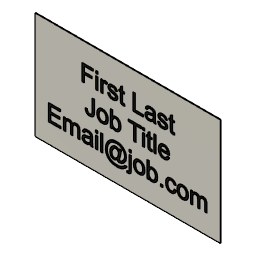
Braille Embosser Assembly v1.0 (Autodesk Fusion 360 archive; units mm, degrees)
design "Business Card v1.0 (Non-Working Example)"
Autodesk Fusion 360 part; units mm, degrees
note: some values were not read from the file. Set by a fixed rule: which face or edge a step refers to.
sketch "Sketch1" plane through (0, 0, 0) normal (0, 1, 0) x (1, 0, 0)
  line L0 (0, 0) -> (90, 0)
  line L1 (90, 0) -> (90, -52)
  line L2 (90, -52) -> (0, -52)
  line L3 (0, -52) -> (0, 0)
  dimension "d1" = 90
  dimension "d2" = 52
  constraint horizontal L0
  constraint vertical L1
  constraint horizontal L2
  constraint vertical L3
  constraint coincident L0.start L3.end
  measures "d1" distance of L0.start L0.end
  measures "d2" distance of L0.start L2.end
extrude "Extrude1" add sketch "Sketch1" along normal blind 0.3 makes body 1
sketch "Sketch2" plane through (0, 0, 0) normal (0, -1, 0) x (1, 0, 0)
  line L0 (90, 52) -> (0, 52)
  line L1 (0, 52) -> (0, 0)
  line L2 (0, 0) -> (90, 0)
  line L3 (90, 0) -> (90, 52)
  line L4 (0, 0) -> (90, 0) construction
  line L5 (90, 0) -> (90, 52) construction
  line L6 (90, 52) -> (0, 52) construction
  line L7 (0, 52) -> (0, 0) construction
  dimension "d5" = 8
  text T0 "First Last\nJob Title\nEmail@job.com" font "Arial" height 8 align centre middle in box 90 x 52 at (0, 0) x (1, 0) y (0, 1) spacing 1 kerned
  constraint coincident L2.end
  constraint coincident L0.end
extrude "Extrude2" cut sketch "Sketch2" against normal blind 0.15 text T0 bodies 1
extrude "Extrude3" add 34 faces at (23.211, 0.15, 38.3638) (30.1651, 0.15, 36.4175) (30.1651, 0.15, 41.7326) (32.3042, 0.15, 37.4288) (38.3852, 0.15, 37.4715) (42.1287, 0.15, 37.276) (47.9422, 0.15, 37.467) (58.0793, 0.15, 36.1309) (62.6143, 0.15, 37.4715) (66.3579, 0.15, 37.276) (28.1223, 0.15, 26.3456) (30.4331, 0.15, 25.2981) (36.9467, 0.15, 25.7442) (48.6335, 0.15, 24.352) (52.839, 0.15, 23.9318) (52.839, 0.15, 29.2469) (55.493, 0.15, 24.7904) (58.3997, 0.15, 24.6667) (63.4748, 0.15, 24.9159) (75.884, 0.15, 12.4484) (69.3417, 0.15, 12.8125) (64.2309, 0.15, 10.6585) (54.7311, 0.15, 13.2585) (48.2176, 0.15, 12.8125) (46.3834, 0.15, 11.2424) (46.3834, 0.15, 16.754) (41.3302, 0.15, 13.769) (32.5389, 0.15, 12.181) (30.0832, 0.15, 16.7613) (30.0832, 0.15, 11.4461) (27.5636, 0.15, 11.1595) (14.2251, 0.15, 12.4484) (6.9436, 0.15, 13.4034) (61.6721, 0.15, 9.8872) along direction (0, -1, 0) blind 0.15 separate body on bodies 1 makes body 2 at (6.9436, 0.15, 13.4034) makes body 3 at (27.5636, 0.15, 11.1595) makes body 4 at (30.0832, 0.15, 16.7613) makes body 5 at (41.3302, 0.15, 13.769) makes body 6 at (46.3834, 0.15, 11.2424) makes body 7 at (54.7311, 0.15, 13.2585) makes body 8 at (69.3417, 0.15, 12.8125) makes body 9 at (63.4748, 0.15, 24.9159) makes body 10 at (55.493, 0.15, 24.7904) makes body 11 at (52.839, 0.15, 23.9318) makes body 12 at (36.9467, 0.15, 25.7442) makes body 13 at (28.1223, 0.15, 26.3456) makes body 14 at (62.6143, 0.15, 37.4715) makes body 15 at (47.9422, 0.15, 37.467) makes body 16 at (38.3852, 0.15, 37.4715) makes body 17 at (30.1651, 0.15, 41.7326) makes body 18 at (23.211, 0.15, 38.3638) makes body 19 at (30.1651, 0.15, 36.4175) makes body 20 at (32.3042, 0.15, 37.4288) makes body 21 at (42.1287, 0.15, 37.276) makes body 22 at (58.0793, 0.15, 36.1309) makes body 23 at (66.3579, 0.15, 37.276) makes body 24 at (30.4331, 0.15, 25.2981) makes body 25 at (48.6335, 0.15, 24.352) makes body 26 at (52.839, 0.15, 29.2469) makes body 27 at (58.3997, 0.15, 24.6667) makes body 28 at (75.884, 0.15, 12.4484) makes body 29 at (64.2309, 0.15, 10.6585) makes body 30 at (48.2176, 0.15, 12.8125) makes body 31 at (46.3834, 0.15, 16.754) makes body 32 at (32.5389, 0.15, 12.181) makes body 33 at (30.0832, 0.15, 11.4461) makes body 34 at (14.2251, 0.15, 12.4484) makes body 35 at (61.6721, 0.15, 9.8872)
equation "d6 = 'First Last Job Title Email@job.com'"
